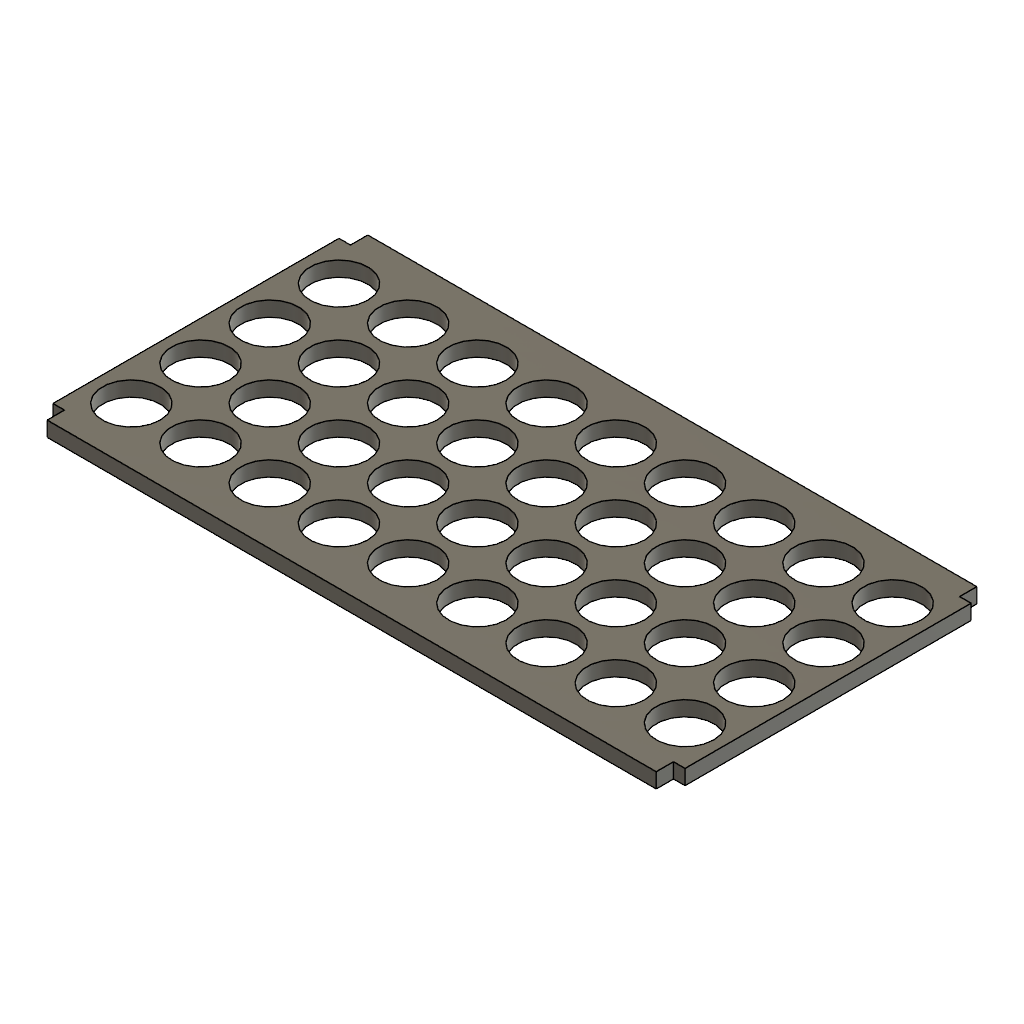
02-06_받침판 (Autodesk Fusion 360 design; units mm, degrees)
Autodesk Fusion 360 part; units mm, degrees
sketch "스케치1" plane through (0, 0, 0) normal (0, 1, 0) x (1, 0, 0)
  line L0 (-54.8, 27.8) -> (54.8, 27.8)
  line L1 (54.8, 27.8) -> (54.8, -27.8)
  line L2 (54.8, -27.8) -> (-54.8, -27.8)
  line L3 (-54.8, -27.8) -> (-54.8, 27.8)
  line L4 (0, 27.8) -> (0, -27.8) construction
  line L5 (-54.8, 0) -> (54.8, 0) construction
  dimension "d1" = 109.6
  dimension "d3" = 55.6
  constraint horizontal L0
  constraint vertical L1
  constraint horizontal L2
  constraint vertical L3
  constraint midpoint L0 L4.start
  constraint midpoint L2 L4.end
  constraint midpoint L3 L5.start
  constraint midpoint L1 L5.end
  constraint coincident origin L4
  constraint coincident origin L5
  measures "d1" distance of L0.start L0.end
  measures "d3" distance of L0.end L1.end
extrude "돌출1" add sketch "스케치1" along normal blind 2.6
sketch "스케치2" plane through (0, 2.6, 0) normal (0, 1, 0) x (-1, 0, 0)
  line L0 (54.8, 27.8) -> (-54.8, 27.8)
  line L1 (-54.8, 27.8) -> (-54.8, -27.8)
  line L2 (-54.8, -27.8) -> (54.8, -27.8)
  line L3 (54.8, -27.8) -> (54.8, 27.8)
  line L4 (-54.8, -27.8) -> (-52.8, -27.8)
  line L5 (-52.8, -27.8) -> (-52.8, -24.8)
  line L6 (-52.8, -24.8) -> (-54.8, -24.8)
  line L7 (-54.8, -24.8) -> (-54.8, -27.8)
  line L8 (-54.8, 27.8) -> (-52.8, 27.8)
  line L9 (-52.8, 27.8) -> (-52.8, 24.8)
  line L10 (-52.8, 24.8) -> (-54.8, 24.8)
  line L11 (-54.8, 24.8) -> (-54.8, 27.8)
  line L12 (54.8, 27.8) -> (52.8, 27.8)
  line L13 (52.8, 27.8) -> (52.8, 24.8)
  line L14 (52.8, 24.8) -> (54.8, 24.8)
  line L15 (54.8, 24.8) -> (54.8, 27.8)
  line L16 (54.8, -27.8) -> (52.8, -27.8)
  line L17 (52.8, -27.8) -> (52.8, -24.8)
  line L18 (52.8, -24.8) -> (54.8, -24.8)
  line L19 (54.8, -24.8) -> (54.8, -27.8)
  dimension "d6" = 2
  dimension "d7" = 3
  dimension "d8" = 2
  dimension "d9" = 3
  dimension "d10" = 2
  dimension "d11" = 3
  dimension "d12" = 2
  dimension "d13" = 3
  constraint horizontal L4
  constraint vertical L5
  constraint horizontal L6
  constraint vertical L7
  constraint coincident L1.end L2.start
  constraint horizontal L8
  constraint vertical L9
  constraint horizontal L10
  constraint vertical L11
  constraint coincident L0.end L1.start
  constraint horizontal L12
  constraint vertical L13
  constraint horizontal L14
  constraint vertical L15
  constraint coincident L0.start L3.end
  constraint horizontal L16
  constraint vertical L17
  constraint horizontal L18
  constraint vertical L19
  constraint coincident L2.end L3.start
  measures "d6" distance of L1.end L4.end
  measures "d7" distance of L1.end L6.end
  measures "d8" distance of L0.end L8.end
  measures "d9" distance of L0.end L10.end
  measures "d10" distance of L0.start L12.end
  measures "d11" distance of L0.start L14.end
  measures "d12" distance of L2.end L16.end
  measures "d13" distance of L2.end L18.end
extrude "돌출2" cut sketch "스케치2" against normal blind 2.6 contours L0 L3 L12 L13 L14 L15 | L0 L1 L8 L9 L10 L11 | L2 L3 L16 L17 L18 L19 | L1 L2 L4 L5 L6 L7
sketch "스케치3" plane through (0, 2.6, 0) normal (0, 1, 0) x (-1, 0, 0)
  line L0 (52.8, -27.8) -> (52.8, -24.8)
  line L1 (52.8, -24.8) -> (54.8, -24.8)
  line L2 (54.8, -24.8) -> (54.8, 24.8)
  line L3 (54.8, 24.8) -> (52.8, 24.8)
  line L4 (52.8, 24.8) -> (52.8, 27.8)
  line L5 (52.8, 27.8) -> (-52.8, 27.8)
  line L6 (-52.8, 27.8) -> (-52.8, 24.8)
  line L7 (-52.8, 24.8) -> (-54.8, 24.8)
  line L8 (-54.8, 24.8) -> (-54.8, -24.8)
  line L9 (-54.8, -24.8) -> (-52.8, -24.8)
  line L10 (-52.8, -24.8) -> (-52.8, -27.8)
  line L11 (-52.8, -27.8) -> (52.8, -27.8)
  circle A0 centre (-48, -18) radius 5
  circle A1 centre (-36, -18) radius 5
  circle A2 centre (-24, -18) radius 5
  circle A3 centre (-12, -18) radius 5
  circle A4 centre (0, -18) radius 5
  circle A5 centre (12, -18) radius 5
  circle A6 centre (24, -18) radius 5
  circle A7 centre (36, -18) radius 5
  circle A8 centre (48, -18) radius 5
  circle A9 centre (-48, -6) radius 5
  circle A10 centre (-36, -6) radius 5
  circle A11 centre (-24, -6) radius 5
  circle A12 centre (-12, -6) radius 5
  circle A13 centre (0, -6) radius 5
  circle A14 centre (12, -6) radius 5
  circle A15 centre (24, -6) radius 5
  circle A16 centre (36, -6) radius 5
  circle A17 centre (48, -6) radius 5
  circle A18 centre (-48, 6) radius 5
  circle A19 centre (-36, 6) radius 5
  circle A20 centre (-24, 6) radius 5
  circle A21 centre (-12, 6) radius 5
  circle A22 centre (0, 6) radius 5
  circle A23 centre (12, 6) radius 5
  circle A24 centre (24, 6) radius 5
  circle A25 centre (36, 6) radius 5
  circle A26 centre (48, 6) radius 5
  circle A27 centre (-48, 18) radius 5
  circle A28 centre (-36, 18) radius 5
  circle A29 centre (-24, 18) radius 5
  circle A30 centre (-12, 18) radius 5
  circle A31 centre (0, 18) radius 5
  circle A32 centre (12, 18) radius 5
  circle A33 centre (24, 18) radius 5
  circle A34 centre (36, 18) radius 5
  circle A35 centre (48, 18) radius 5
  dimension "d16" = 10
  dimension "d19" = 96
  dimension "d20" = 36
  dimension "d21" = 6.8
  dimension "d22" = 9.8
  measures "d16" diameter of A0
  measures "d21" distance of L8 A0.centre
  measures "d22" distance of L11 A0.centre
extrude "돌출3" cut sketch "스케치3" against normal blind 2.6 contours A0 | A1 | A2 | A3 | A4 | A5 | A6 | A7 | A8 | A9 | A10 | A11 | A12 | A13 | A14 | A15 | A16 | A17 | A18 | A19 | A20 | A21 | A22 | A23 | A24 | A25 | A26 | A27 | A28 | A29 | A30 | A31 | A32 | A33 | A34 | A35
